fusion-concept (Autodesk Fusion 360 design; units mm, degrees)
part number: 2026-10-22-20-38-54-611
Autodesk Fusion 360 part; units mm, degrees
sketch "Sketch1" plane through (0, 0, 0) normal (1, 0, 0) x (0, 1, 0)
  line L0 (0, 0) -> (80, 0)
  line L1 (80, 0) -> (110, 0)
  line L2 (110, 0) -> (120, 0)
  line L3 (120, 0) -> (126.0809, 0)
  spline S0 degree 5 poles (126.0809, 0) (125.6545, 0.6874) (124.8112, 2.091) (123.5754, 4.2831) (121.9867, 7.3818) (120.1053, 11.5669) (118.3359, 16.086) (116.6845, 20.9567) (115.1489, 26.1729) (113.7202, 31.7078) (112.388, 37.5306) (111.3922, 42.3974) (110.6821, 46.1569) (110.2247, 48.711) (110, 50) knots 0 0 0 0 0 0 0.1 0.2 0.3 0.4 0.5 0.6 0.7 0.8 0.9 1 1 1 1 1 1
  line L4 (0, 0) -> (0, 220)
  spline S1 degree 5 poles (0, 220) (3.5831, 219.7053) (10.5639, 218.9858) (20.479, 217.5164) (32.5789, 214.7714) (45.8021, 209.9958) (57.1074, 203.833) (66.5301, 196.2448) (74.2042, 187.2174) (80.3962, 176.778) (85.4365, 164.9776) (89.6698, 151.8821) (93.4048, 137.5658) (96.862, 122.109) (100.1848, 105.589) (103.4585, 88.072) (106.0718, 73.3006) (108.0347, 61.8095) (109.3447, 53.9669) (110, 50) knots 0 0 0 0 0 0 0.066667 0.133333 0.2 0.266667 0.333333 0.4 0.466667 0.533333 0.6 0.666667 0.733333 0.8 0.866667 0.933333 1 1 1 1 1 1
  line L5 (0, 220) -> (0, 230)
  line L6 (0, 220) -> (0, 230)
  line L7 (0, 230) -> (0, 238.1262)
  spline S2 degree 5 poles (0, 238.1262) (2.0863, 237.7409) (6.2194, 236.9326) (12.2999, 235.6072) (20.1652, 233.6104) (29.5653, 230.705) (38.4918, 227.3504) (46.9005, 223.5045) (54.758, 219.1356) (62.0717, 214.2509) (68.8768, 208.8838) (73.9445, 204.2329) (77.5465, 200.5562) (79.861, 198.0227) (80.9965, 196.7353) knots 0 0 0 0 0 0 0.1 0.2 0.3 0.4 0.5 0.6 0.7 0.8 0.9 1 1 1 1 1 1
  spline S3 degree 5 poles (80.9965, 196.7353) (81.8749, 195.4749) (83.6118, 192.7432) (86.1571, 188.0127) (89.43, 180.4305) (93.3167, 168.8065) (97, 155.0714) (100.4891, 139.3724) (103.808, 122.0481) (106.9982, 103.6632) (110.1115, 84.9141) (113.205, 66.5666) (116.3358, 49.3869) (119.5559, 34.071) (122.9075, 21.1811) (126.4156, 11.0419) (129.3543, 5.2083) (131.6329, 2.111) (133.1848, 0.6097) (133.969, 0) knots 0 0 0 0 0 0 0.066667 0.133333 0.2 0.266667 0.333333 0.4 0.466667 0.533333 0.6 0.666667 0.733333 0.8 0.866667 0.933333 1 1 1 1 1 1
  line L8 (126.0809, 0) -> (133.969, 0)
  line L9 (127.7369, 0) -> (133.969, 0)
  line L10 (0, 220) -> (0, 110)
  line L11 (30, 110) -> (0, 110)
  point P0 (117.6749, 18.1251)
  point P1 (64.6373, 197.2546)
  point P2 (90, 150)
  point P3 (49.0572, 222.1829)
  point P4 (99.433, 143.7628)
  point P5 (121.2551, 27.9286)
  dimension "d1" = 80
  dimension "d2" = 30
  dimension "d3" = 220
  constraint coincident L0.start L4.start
  constraint horizontal L0
  constraint parallel L0 L1
  constraint parallel L1 L2
  constraint parallel L2 L3
  constraint perpendicular L0 L4
  constraint parallel L4 L5
  constraint parallel L6 L7
  constraint parallel L3 L8
  constraint coincident L3 L9.start
  constraint coincident L8 S3.end
  constraint midpoint L4 L10.end
  constraint perpendicular L4 L11
  measures "d1" distance of L0.start L0.end
  measures "d2" distance of L0.end L1.end
  measures "d3" distance of L0.start L4.end
revolve "Revolve1" add sketch "Sketch1" angle 360 about axis through (0, 0, 0) along (0, 0, 1) contours S0 S1 L5 L6 L7 S2 S3 L8 L9
sketch "Sketch3" plane through (0, 0, 0) normal (1, 0, 0) x (0, 1, 0)
  spline S0 degree 5 poles (0, 140) (0.5737, 142.0777) (1.7671, 146.128) (3.6951, 151.8884) (6.6968, 158.815) (11.9332, 165.5709) (19.3997, 169.7181) (29.4234, 170.7686) (41.5147, 168.7305) (53.9551, 164.3941) (64.4633, 158.9852) (70.8478, 153.8245) (71.6948, 149.9731) (66.9771, 147.9123) (58.8888, 147.1278) (50.792, 146.5023) (45.9258, 144.8148) (46.095, 141.2377) (50.6597, 135.731) (57.6338, 128.7002) (64.5307, 120.7428) (69.2916, 112.3648) (71.2039, 103.7031) (70.5648, 94.6458) (68.3181, 84.9607) (65.6973, 74.4249) (63.893, 62.9428) (63.6528, 50.6965) (65.1043, 38.1914) (67.9905, 26.1047) (71.8106, 15.1785) (75.1601, 7.9122) (77.6237, 3.5203) (79.2162, 1.0904) (80, 0) knots 0 0 0 0 0 0 0.033333 0.066667 0.1 0.133333 0.166667 0.2 0.233333 0.266667 0.3 0.333333 0.366667 0.4 0.433333 0.466667 0.5 0.533333 0.566667 0.6 0.633333 0.666667 0.7 0.733333 0.766667 0.8 0.833333 0.866667 0.9 0.933333 0.966667 1 1 1 1 1 1
  line L0 (80, 0) -> (0, 0)
  line L1 (0, 0) -> (0, 140)
  line L2 (-80, 0) -> (0, 0)
  spline S1 degree 5 poles (0, 140) (-0.5737, 142.0777) (-1.7671, 146.128) (-3.6951, 151.8884) (-6.6968, 158.815) (-11.9332, 165.5709) (-19.3997, 169.7181) (-29.4234, 170.7686) (-41.5147, 168.7305) (-53.9551, 164.3941) (-64.4633, 158.9852) (-70.8478, 153.8245) (-71.6948, 149.9731) (-66.9771, 147.9123) (-58.8888, 147.1278) (-50.792, 146.5023) (-45.9258, 144.8148) (-46.095, 141.2377) (-50.6597, 135.731) (-57.6338, 128.7002) (-64.5307, 120.7428) (-69.2916, 112.3648) (-71.2039, 103.7031) (-70.5648, 94.6458) (-68.3181, 84.9607) (-65.6973, 74.4249) (-63.893, 62.9428) (-63.6528, 50.6965) (-65.1043, 38.1914) (-67.9905, 26.1047) (-71.8106, 15.1785) (-75.1601, 7.9122) (-77.6237, 3.5203) (-79.2162, 1.0904) (-80, 0) knots 0 0 0 0 0 0 0.033333 0.066667 0.1 0.133333 0.166667 0.2 0.233333 0.266667 0.3 0.333333 0.366667 0.4 0.433333 0.466667 0.5 0.533333 0.566667 0.6 0.633333 0.666667 0.7 0.733333 0.766667 0.8 0.833333 0.866667 0.9 0.933333 0.966667 1 1 1 1 1 1
  line L3 (-7.413, 113.1546) -> (7.413, 166.8454)
  line L4 (71.856, 11.3304) -> (88.144, -11.3304)
  line L5 (7.413, 113.1546) -> (-7.413, 166.8454)
  line L6 (-71.856, 11.3304) -> (-88.144, -11.3304)
  point P0 (30, 170)
  point P1 (70, 150)
  point P2 (47.5667, 144.7344)
  point P3 (64.1515, 120.4291)
  point P4 (64.7234, 66.9574)
  point P5 (-70, 150)
  point P6 (-30, 170)
  point P7 (-70, 150)
  point P8 (-47.5667, 144.7344)
  point P9 (-64.1515, 120.4291)
  point P10 (-64.7234, 66.9574)
  constraint coincident L0.end L1.start
  constraint horizontal L0
  constraint perpendicular L0 L1
  constraint symmetric P1 L1 P7
  constraint symmetric S0.end L1 L2.start
  constraint symmetric L0.end L1 L2.end
  constraint midpoint S0.start L3
  constraint midpoint S0.end L4
  constraint symmetric S0.start L1 S1.start
  constraint symmetric P0 L1 P6
  constraint symmetric P2 L1 P8
  constraint symmetric P3 L1 P9
  constraint symmetric P4 L1 P10
  constraint symmetric L1 L3.start L5.start
  constraint symmetric L1 L3.end L5.end
  constraint symmetric L1 L4.start L6.start
  constraint symmetric L1 L4.end L6.end
extrude "Extrude1" cut sketch "Sketch3" along normal blind 190
